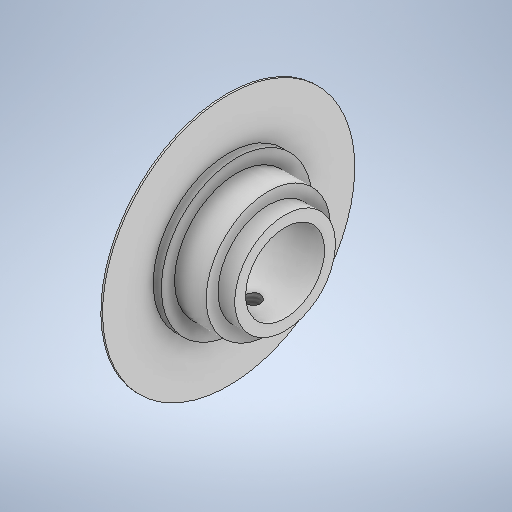
# Autodesk Inventor part: tarcza
Saved by Autodesk Inventor 2025.2 (Build 292293000, 293)
## iProperties
Created: 2025-04-07
Part Number: tarcza
Material: Ogólny
Document SubType Name: Modeling
Designer: Jan Bołtralik
Density: 1 g/cm^3
Appearance: Domyślna
Author: Jan Bołtralik
Autodesk Inventor part; units mm, degrees
ref_plane "YZ Plane" through (0, 0, 0) normal (1, 0, 0) x (0, 1, 0)
ref_plane "XY Plane" through (0, 0, 0) normal (0, 0, 1) x (1, 0, 0)
sketch "Szkic1" plane through (0, 0, 0) normal (0, 0, 1) x (1, 0, 0)
  line L0 (0, -1.4382) -> (10, -1.4382)
  line L1 (0, 2.5618) -> (0, 11.3418)
  line L2 (0, 11.3418) -> (0.18, 11.3418)
  line L3 (0.18, 11.3418) -> (0.18, 6.2118)
  line L4 (0.18, 6.2118) -> (1, 6.2118)
  line L5 (1, 6.2118) -> (1, 4.8618)
  line L6 (1, 4.8618) -> (4.2, 4.8618)
  line L7 (4.2, 4.8618) -> (4.2, 3.6618)
  line L8 (4.2, 3.6618) -> (5.9, 3.6618)
  line L9 (5.9, 3.6618) -> (5.9, 2.5618)
  line L10 (0, 2.5618) -> (5.9, 2.5618)
  dimension "d0" = 10
  dimension "d1" = 25.56
  dimension "d2" = 15.3
  dimension "d3" = 12.6
  dimension "d4" = 10.2
  dimension "d5" = 0.18
  dimension "d6" = 1
  dimension "d7" = 4.2
  dimension "d8" = 5.9
  dimension "d9" = 8
  constraints: 22 end point, 9 perpendicular, 1 horizontal, 1 vertical
  measures "d0" distance of L0.start L0.end
  measures "d1" diameter of L2 L0
  measures "d2" diameter of L4 L0
  measures "d3" diameter of L6 L0
  measures "d4" diameter of L8 L0
  measures "d5" distance between parallel lines of L3 L1
  measures "d6" distance between parallel lines of L5 L1
  measures "d7" distance between parallel lines of L7 L1
  measures "d8" distance between parallel lines of L9 L1
  measures "d9" diameter of L10 L0
revolve "Obrót1" add sketch "Szkic1" angle 360 about axis through (0, -1.4382, 0) along (1, 0, 0)
ref_plane "Płaszczyzna konstrukcyjna1" through (2.6, -7.7382, 0) normal (0, 1, 0) x (-1, 0, 0)
sketch "Szkic2" plane through (2.6, -7.7382, 0) normal (0, 1, 0) x (-1, 0, 0)
  line L0 (1.6, 6.3) -> (1.6, -6.3) projected
  line L1 (-1.6, 6.3) -> (-1.6, -6.3) projected
  line L2 (1.6, 6.3) -> (-1.6, -6.3)
  line L3 (1.6, -6.3) -> (-1.6, 6.3)
  point P0 (0, 0)
  constraints: 4 end point, 1 midpoint
hole "Otwór1" at (2.6, -7.7382, 0) direction (0, 1, 0) diameter 1.567 depth 3.15 tip angle 118 countersink diameter 2.1 countersink angle 90 thread size "M2x0.4" class "6H" standard "ISO Metric profile"
